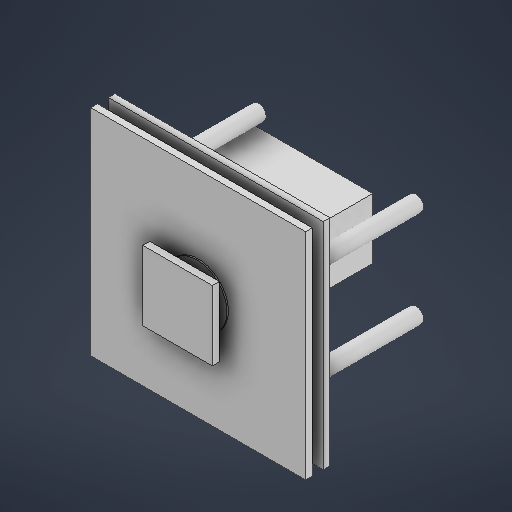
# Autodesk Inventor part: 04_Mam_Xoay_Bi_Sat_71x71_MG996R_360_AS5600
Saved by Autodesk Inventor 2027.1 (Build 311270010, 270A)
## iProperties
Created: 2026-11-18
Part Number: 04_Mam_Xoay_Bi_Sat_71x71_MG996R_360_AS5600
Material: Generic
Document SubType Name: Modeling
Designer: cuong
Density: 1 g/cm^3
Appearance: Default
Author: cuong
Autodesk Inventor part; units mm, degrees
ref_plane "Work Plane1" through (0, 0, 175) normal (0, 0, 1) x (1, 0, 0)
sketch "Sketch1" plane through (0, 0, 175) normal (0, 0, 1) x (1, 0, 0)
  line L0 (9.5, 89.5) -> (80.5, 89.5)
  line L1 (80.5, 89.5) -> (80.5, 160.5)
  line L2 (80.5, 160.5) -> (9.5, 160.5)
  line L3 (9.5, 160.5) -> (9.5, 89.5)
  constraints: 8 end point, 2 parallel, 1 horizontal, 1 perpendicular
extrude "Extrusion1" add sketch "Sketch1" along normal blind 2.2
ref_plane "Work Plane2" through (0, 0, 177.2) normal (0, 0, 1) x (1, 0, 0)
sketch "Sketch2" plane through (0, 0, 177.2) normal (0, 0, 1) x (1, 0, 0)
  circle A0 centre (45, 125) radius 27
  constraints: 1 centre point
extrude "Extrusion2" add sketch "Sketch2" along normal blind 3.6
ref_plane "Work Plane3" through (0, 0, 180.8) normal (0, 0, 1) x (1, 0, 0)
sketch "Sketch3" plane through (0, 0, 180.8) normal (0, 0, 1) x (1, 0, 0)
  line L0 (9.5, 89.5) -> (80.5, 89.5)
  line L1 (80.5, 89.5) -> (80.5, 160.5)
  line L2 (80.5, 160.5) -> (9.5, 160.5)
  line L3 (9.5, 160.5) -> (9.5, 89.5)
  constraints: 8 end point, 2 parallel, 1 horizontal, 1 perpendicular
extrude "Extrusion3" add sketch "Sketch3" along normal blind 2.2
ref_plane "Work Plane4" through (0, 0, 137) normal (0, 0, 1) x (1, 0, 0)
sketch "Sketch4" plane through (0, 0, 137) normal (0, 0, 1) x (1, 0, 0)
  circle A0 centre (19, 109) radius 2.5
  constraints: 1 centre point
extrude "Extrusion4" add sketch "Sketch4" along normal blind 38
ref_plane "Work Plane5" through (0, 0, 137) normal (0, 0, 1) x (1, 0, 0)
sketch "Sketch5" plane through (0, 0, 137) normal (0, 0, 1) x (1, 0, 0)
  circle A0 centre (19, 141) radius 2.5
  constraints: 1 centre point
extrude "Extrusion5" add sketch "Sketch5" along normal blind 38
ref_plane "Work Plane6" through (0, 0, 137) normal (0, 0, 1) x (1, 0, 0)
sketch "Sketch6" plane through (0, 0, 137) normal (0, 0, 1) x (1, 0, 0)
  circle A0 centre (71, 109) radius 2.5
  constraints: 1 centre point
extrude "Extrusion6" add sketch "Sketch6" along normal blind 38
ref_plane "Work Plane7" through (0, 0, 137) normal (0, 0, 1) x (1, 0, 0)
sketch "Sketch7" plane through (0, 0, 137) normal (0, 0, 1) x (1, 0, 0)
  circle A0 centre (71, 141) radius 2.5
  constraints: 1 centre point
extrude "Extrusion7" add sketch "Sketch7" along normal blind 38
ref_plane "Work Plane8" through (0, 0, 161) normal (0, 0, 1) x (1, 0, 0)
sketch "Sketch8" plane through (0, 0, 161) normal (0, 0, 1) x (1, 0, 0)
  line L0 (7, 107) -> (65, 107)
  line L1 (65, 107) -> (65, 143)
  line L2 (65, 143) -> (7, 143)
  line L3 (7, 143) -> (7, 107)
  constraints: 8 end point, 2 parallel, 1 horizontal, 1 perpendicular
extrude "Extrusion8" add sketch "Sketch8" along normal blind 2.5
ref_plane "Work Plane9" through (0, 0, 135.5) normal (0, 0, 1) x (1, 0, 0)
sketch "Sketch9" plane through (0, 0, 135.5) normal (0, 0, 1) x (1, 0, 0)
  line L0 (14.85, 115) -> (55.15, 115)
  line L1 (55.15, 115) -> (55.15, 135)
  line L2 (55.15, 135) -> (14.85, 135)
  line L3 (14.85, 135) -> (14.85, 115)
  constraints: 8 end point, 2 parallel, 1 horizontal, 1 perpendicular
extrude "Extrusion9" add sketch "Sketch9" along normal blind 36.6
ref_plane "Work Plane10" through (0, 0, 162.1) normal (0, 0, 1) x (1, 0, 0)
sketch "Sketch10" plane through (0, 0, 162.1) normal (0, 0, 1) x (1, 0, 0)
  line L0 (8.2, 115.25) -> (61.8, 115.25)
  line L1 (61.8, 115.25) -> (61.8, 134.75)
  line L2 (61.8, 134.75) -> (8.2, 134.75)
  line L3 (8.2, 134.75) -> (8.2, 115.25)
  constraints: 8 end point, 2 parallel, 1 horizontal, 1 perpendicular
extrude "Extrusion10" add sketch "Sketch10" along normal blind 2.5
ref_plane "Work Plane11" through (0, 0, 172.1) normal (0, 0, 1) x (1, 0, 0)
sketch "Sketch11" plane through (0, 0, 172.1) normal (0, 0, 1) x (1, 0, 0)
  circle A0 centre (45, 125) radius 6
  constraints: 1 centre point
extrude "Extrusion11" add sketch "Sketch11" along normal blind 4
ref_plane "Work Plane12" through (0, 0, 176.1) normal (0, 0, 1) x (1, 0, 0)
sketch "Sketch12" plane through (0, 0, 176.1) normal (0, 0, 1) x (1, 0, 0)
  circle A0 centre (45, 125) radius 3
  constraints: 1 centre point
extrude "Extrusion12" add sketch "Sketch12" along normal blind 7
ref_plane "Work Plane13" through (0, 0, 181) normal (0, 0, 1) x (1, 0, 0)
sketch "Sketch13" plane through (0, 0, 181) normal (0, 0, 1) x (1, 0, 0)
  circle A0 centre (45, 125) radius 10
  constraints: 1 centre point
extrude "Extrusion13" add sketch "Sketch13" along normal blind 2.5
ref_plane "Work Plane14" through (0, 0, 183.5) normal (0, 0, 1) x (1, 0, 0)
sketch "Sketch14" plane through (0, 0, 183.5) normal (0, 0, 1) x (1, 0, 0)
  circle A0 centre (45, 125) radius 4
  constraints: 1 centre point
extrude "Extrusion14" add sketch "Sketch14" along normal blind 2.5
ref_plane "Work Plane15" through (0, 0, 187.5) normal (0, 0, 1) x (1, 0, 0)
sketch "Sketch15" plane through (0, 0, 187.5) normal (0, 0, 1) x (1, 0, 0)
  line L0 (33.5, 113.5) -> (56.5, 113.5)
  line L1 (56.5, 113.5) -> (56.5, 136.5)
  line L2 (56.5, 136.5) -> (33.5, 136.5)
  line L3 (33.5, 136.5) -> (33.5, 113.5)
  constraints: 8 end point, 2 parallel, 1 horizontal, 1 perpendicular
extrude "Extrusion15" add sketch "Sketch15" along normal blind 2.3
body "Solid1"
